Autodesk Fusion 360 part; units mm, degrees
(part 2 of 2)
equation "bolt_line_y = pod_d / 2 - skin_t - bond_t - tube_d / 2" comment "CONFIRMED: J-WALL-02 bolt line on the back panel's tube centre, Y 824 (joints register R-J15, FR-07)"
equation "rivnut_d = 9.53 mm" comment "SOURCE: Sherex CAH3-610-4.2 hole 9.53 +0.10 (HW-SEL A5; register H-03)"
equation "spigot_d = 8.5 mm" comment "ASSUMPTION: register FR-05: hole for the 8 mm locating spigot H-05"
equation "spigot_slot = 14 mm" comment "ASSUMPTION: register FR-05: slot length for the second spigot"
equation "spigot_edge = spigot_inset" comment "CALCULATION: the skeleton's spigot_inset: spigots 100 from each end of the edge (PM ruling 2026-10-31, R-J13)"
equation "bolt_edge = bolt_edge_inset" comment "CALCULATION: the skeleton's bolt_edge_inset: end bolts 220 in from the panel's ends, evenly spaced, every bolt 30 or more from any stile (PM ruling 2026-10-31, R-J14)"
equation "n_side_jnt = 3" comment "SOURCE: register J-WALL-02, J-FRONT-01: 3 bolts up each side panel"
equation "side_jnt_pitch = ( pnl_h - 2 * bolt_edge ) / ( n_side_jnt - 1 )" comment "CALCULATION: equal pitch of the 3 bolts up the corner and decor joints"
equation "pocket_w = 60 mm" comment "ASSUMPTION: register FR-10: fill left out 60 x 60 next to each bolt for the key"
equation "corner_z0 = panel_z0 + back_ph + seam_gap" comment "CALCULATION: bottom of the back panel row this side panel meets at the corner (B1/B2 or B3/B4, skeleton P04)"
equation "corner_bolt_pitch = ( back_ph - 2 * bolt_edge ) / ( n_side_jnt - 1 )" comment "CALCULATION: J-WALL-02 bolts run along the back panel's edge: 220, 559.31, 898.61 on its 1118.61 (joints register 2.9)"
equation "n_len_bolt = n_base_bolt" comment "CALCULATION: the skeleton's n_base_bolt (4): the same count on J-WALL-01 and the J-CEIL-01 side edges (register 2.9)"
equation "ceil_bolt_pitch = ( wall_depth - 2 * bolt_edge ) / ( n_len_bolt - 1 )" comment "CALCULATION: J-CEIL-01 side edge: 4 bolts along the ceiling's 1495 from Y -645 (its front edge), 220 rule, pitch 351.67 on P04; CEILING drills the same (PM ruling 2026-10-31 16:55; joints register 2.9)"
equation "len_bolt_pitch = ( pnl_len - 2 * bolt_edge ) / ( n_len_bolt - 1 )" comment "CALCULATION: even pitch of the bolts along the panel"
equation "felt_t = 9 mm" comment "SOURCE: plan VT03-PET 9 mm PET felt; HW-SEL A3; D-31 (the factory's felt)"
equation "tray_t = 0.5 mm" comment "CONFIRMED: D-37: galvanised steel tray 0.5 mm"
equation "tray_h = cass_t" comment "CONFIRMED: PM ruling 2026-10-31 (WALL group, option 1): the wall cassettes use the ceiling's tray, returns the full cassette depth (34) turned in as lips that hold the felt, no ribs; settles H09 for the walls"
equation "lip_w = 12 mm" comment "CONFIRMED: PM ruling 2026-10-31 (WALL group, option 1): 12 mm lips hold the felt edge"
equation "bend_r = tray_t" comment "ASSUMPTION: inside bend radius 1 x t for 0.5 mm DX51D (the sheet metal rule's bend radius is its Thickness); the factory's tooling sets it (guideline 9)"
equation "felt_c = 1 mm" comment "ASSUMPTION: felt edge clearance inside the returns, as the ceiling cassette"
equation "gap_h = tray_h - felt_t - 2 * tray_t" comment "CALCULATION: air gap between the tray base and the felt (24): the acoustic gap (D-17) and the cable path (D-26)"
equation "cass_len = wall_depth - stack_t + cass_t" comment "CALCULATION: = 1448: from the decor back plate to past the back cassette's face, closing the inside corner (D-57)"
equation "cass_h = pod_h - outer_t - lin_gap - ( panel_z0 + side_h + seam_gap )" comment "CALCULATION: lower: the panel height; upper: stops lin_gap under the roof frame so it floats (D-57)"
equation "clip_zone_h = 60 mm" comment "ASSUMPTION: height of each reserved clip zone (H03: no clip named)"
equation "clip_zone_dz = 100 mm" comment "ASSUMPTION: clip zone centre from the cassette's top and bottom edges (H03)"
equation "stopw_od = 20 mm" comment "SOURCE: joints register H-08: stop washer Ø10.5 x Ø20 x 1.5 (PROPOSED part)"
equation "stopw_id = 10.5 mm" comment "SOURCE: joints register H-08"
equation "stopw_t = 1.5 mm" comment "SOURCE: joints register H-08: rivnut head 0.76 + washer 1.5 = the 2.26 stop (R-J5)"
equation "rivnut_head_d = 12.96 mm" comment "SOURCE: Sherex CAH3-610-4.2 head Ø12.96 (joints register H-03, SHX)"
equation "rivnut_head_t = 0.76 mm" comment "SOURCE: Sherex CAH3-610-4.2 head 0.76 ±0.08 (H-03, SHX)"
equation "rivnut_body_d = 9.5 mm" comment "SOURCE: Sherex CAH3-610-4.2 body Ø9.50 max (H-03, SHX)"
equation "rivnut_len = 10.16 mm" comment "SOURCE: Sherex CAH3-610-4.2 installed length 10.16 max under the head (H-03, SHX); the bulge inside the tube is not modelled"
equation "m6_d = 6 mm" comment "CALCULATION: M6 threads shown at their 6 mm major diameter (no modelled thread)"
equation "spigot_pin_d = 8 mm" comment "SOURCE: joints register H-05: Ø8 stainless pin (PROPOSED, assumption sizes)"
equation "spigot_proud = 8 mm" comment "SOURCE: joints register H-05: stands 8 proud (read as: of the joint face)"
equation "spigot_thread_l = 10 mm" comment "ASSUMPTION: M6 thread into the spigot rivnut; H-05 gives no length; 10 stays inside the rivnut's 10.16"
equation "d660 = panel_z0 + side_h + seam_gap"
equation "d662 = ( -( pod_w / 2 - outer_t ) ) - ( -( pod_w / 2 - skin_t - bond_t ) )"
equation "d663 = ( pod_d / 2 - skin_t ) - ( pod_d / 2 - wall_depth + seam_gap )"
equation "d664 = abs(-( pod_w / 2 - skin_t - bond_t ))"
equation "d665 = abs(pod_d / 2 - wall_depth + seam_gap)"
equation "d666 = ( ( panel_z0 + side_h + seam_gap ) + tube_w ) - ( panel_z0 + side_h + seam_gap )"
equation "d668 = ( panel_z0 + side_h + seam_gap ) + tube_t"
equation "d670 = ( ( -( pod_w / 2 - outer_t ) ) - tube_t ) - ( ( -( pod_w / 2 - skin_t - bond_t ) ) + tube_t )"
equation "d671 = ( pod_d / 2 - skin_t ) - ( pod_d / 2 - wall_depth + seam_gap )"
equation "d672 = abs(( -( pod_w / 2 - skin_t - bond_t ) ) + tube_t)"
equation "d673 = abs(pod_d / 2 - wall_depth + seam_gap)"
equation "d674 = ( ( ( panel_z0 + side_h + seam_gap ) + tube_w ) - tube_t ) - ( ( panel_z0 + side_h + seam_gap ) + tube_t )"
equation "d676 = ( pod_h ) - top_h"
equation "d678 = ( -( pod_w / 2 - outer_t ) ) - ( -( pod_w / 2 - skin_t - bond_t ) )"
equation "d679 = ( pod_d / 2 - skin_t ) - ( pod_d / 2 - wall_depth + seam_gap )"
equation "d680 = abs(-( pod_w / 2 - skin_t - bond_t ))"
equation "d681 = abs(pod_d / 2 - wall_depth + seam_gap)"
equation "d682 = ( pod_h ) - ( ( pod_h ) - top_h )"
equation "d684 = ( ( pod_h ) - top_h ) + tube_t"
equation "d686 = ( ( -( pod_w / 2 - outer_t ) ) - tube_t ) - ( ( -( pod_w / 2 - skin_t - bond_t ) ) + tube_t )"
equation "d687 = ( pod_d / 2 - skin_t ) - ( pod_d / 2 - wall_depth + seam_gap )"
equation "d688 = abs(( -( pod_w / 2 - skin_t - bond_t ) ) + tube_t)"
equation "d689 = abs(pod_d / 2 - wall_depth + seam_gap)"
equation "d690 = ( ( pod_h ) - tube_t ) - ( ( ( pod_h ) - top_h ) + tube_t )"
equation "d692 = ( panel_z0 + side_h + seam_gap ) + tube_w"
equation "d694 = ( -( pod_w / 2 - outer_t ) ) - ( -( pod_w / 2 - skin_t - bond_t ) )"
equation "d695 = ( ( pod_d / 2 - wall_depth + seam_gap ) + tube_w ) - ( pod_d / 2 - wall_depth + seam_gap )"
equation "d696 = abs(-( pod_w / 2 - skin_t - bond_t ))"
equation "d697 = abs(pod_d / 2 - wall_depth + seam_gap)"
equation "d698 = ( ( pod_h ) - top_h ) - ( ( panel_z0 + side_h + seam_gap ) + tube_w )"
equation "d700 = ( panel_z0 + side_h + seam_gap ) + tube_w"
equation "d702 = ( ( -( pod_w / 2 - outer_t ) ) - tube_t ) - ( ( -( pod_w / 2 - skin_t - bond_t ) ) + tube_t )"
equation "d703 = ( ( ( pod_d / 2 - wall_depth + seam_gap ) + tube_w ) - tube_t ) - ( ( pod_d / 2 - wall_depth + seam_gap ) + tube_t )"
equation "d704 = abs(( -( pod_w / 2 - skin_t - bond_t ) ) + tube_t)"
equation "d705 = abs(( pod_d / 2 - wall_depth + seam_gap ) + tube_t)"
equation "d706 = ( ( pod_h ) - top_h ) - ( ( panel_z0 + side_h + seam_gap ) + tube_w )"
equation "d708 = ( panel_z0 + side_h + seam_gap ) + tube_w"
equation "d710 = ( -( pod_w / 2 - outer_t ) ) - ( -( pod_w / 2 - skin_t - bond_t ) )"
equation "d711 = ( pod_d / 2 - skin_t ) - ( ( pod_d / 2 - skin_t ) - corner_w )"
equation "d712 = abs(-( pod_w / 2 - skin_t - bond_t ))"
equation "d713 = abs(( pod_d / 2 - skin_t ) - corner_w)"
equation "d714 = ( ( pod_h ) - top_h ) - ( ( panel_z0 + side_h + seam_gap ) + tube_w )"
equation "d716 = ( panel_z0 + side_h + seam_gap ) + tube_w"
equation "d718 = ( ( -( pod_w / 2 - outer_t ) ) - tube_t ) - ( ( -( pod_w / 2 - skin_t - bond_t ) ) + tube_t )"
equation "d719 = ( ( pod_d / 2 - skin_t ) - tube_t ) - ( ( ( pod_d / 2 - skin_t ) - corner_w ) + tube_t )"
equation "d720 = abs(( -( pod_w / 2 - skin_t - bond_t ) ) + tube_t)"
equation "d721 = abs(( ( pod_d / 2 - skin_t ) - corner_w ) + tube_t)"
equation "d722 = ( ( pod_h ) - top_h ) - ( ( panel_z0 + side_h + seam_gap ) + tube_w )"
equation "d724 = ( panel_z0 + side_h + seam_gap ) + tube_w"
equation "d726 = ( -( pod_w / 2 - outer_t ) ) - ( -( pod_w / 2 - skin_t - bond_t ) )"
equation "d727 = ( ( pod_d / 2 - wall_depth + seam_gap ) + stile_pitch + tube_w ) - ( ( pod_d / 2 - wall_depth + seam_gap ) + stile_pitch )"
equation "d728 = abs(-( pod_w / 2 - skin_t - bond_t ))"
equation "d729 = abs(( pod_d / 2 - wall_depth + seam_gap ) + stile_pitch)"
equation "d730 = ( ( pod_h ) - top_h ) - ( ( panel_z0 + side_h + seam_gap ) + tube_w )"
equation "d732 = ( panel_z0 + side_h + seam_gap ) + tube_w"
equation "d734 = ( ( -( pod_w / 2 - outer_t ) ) - stud_t ) - ( ( -( pod_w / 2 - skin_t - bond_t ) ) + stud_t )"
equation "d735 = ( ( ( pod_d / 2 - wall_depth + seam_gap ) + stile_pitch + tube_w ) - stud_t ) - ( ( ( pod_d / 2 - wall_depth + seam_gap ) + stile_pitch ) + stud_t )"
equation "d736 = abs(( -( pod_w / 2 - skin_t - bond_t ) ) + stud_t)"
equation "d737 = abs(( ( pod_d / 2 - wall_depth + seam_gap ) + stile_pitch ) + stud_t)"
equation "d738 = ( ( pod_h ) - top_h ) - ( ( panel_z0 + side_h + seam_gap ) + tube_w )"
equation "d740 = stile_n_mid"
equation "d742 = stile_pitch"
equation "d744 = ( panel_z0 + side_h + seam_gap ) + skin_setback"
equation "d746 = ( -( pod_w / 2 - skin_t ) ) - ( -( pod_w / 2 ) )"
equation "d747 = ( pod_d / 2 ) - ( pod_d / 2 - wall_depth + seam_gap )"
equation "d748 = abs(-( pod_w / 2 ))"
equation "d749 = abs(pod_d / 2 - wall_depth + seam_gap)"
equation "d750 = ( pod_h ) - ( ( panel_z0 + side_h + seam_gap ) + skin_setback )"
equation "d752 = ( panel_z0 + side_h + seam_gap ) + skin_setback"
equation "d754 = ( -( pod_w / 2 - skin_t - skin_ret ) ) - ( -( pod_w / 2 - skin_t ) )"
equation "d755 = ( pod_d / 2 ) - ( pod_d / 2 - skin_t )"
equation "d756 = abs(-( pod_w / 2 - skin_t ))"
equation "d757 = abs(pod_d / 2 - skin_t)"
equation "d758 = ( pod_h ) - ( ( panel_z0 + side_h + seam_gap ) + skin_setback )"
equation "d760 = ( panel_z0 + side_h + seam_gap ) + tube_w"
equation "d762 = ( -( pod_w / 2 - outer_t ) ) - ( -( pod_w / 2 - skin_t - bond_t ) )"
equation "d763 = ( ( pod_d / 2 - wall_depth + seam_gap ) + stile_pitch ) - ( ( pod_d / 2 - wall_depth + seam_gap ) + tube_w )"
equation "d764 = abs(-( pod_w / 2 - skin_t - bond_t ))"
equation "d765 = abs(( pod_d / 2 - wall_depth + seam_gap ) + tube_w)"
equation "d766 = ( ( pod_h ) - top_h ) - ( ( panel_z0 + side_h + seam_gap ) + tube_w )"
equation "d768 = stile_n_mid"
equation "d770 = stile_pitch"
equation "d772 = ( panel_z0 + side_h + seam_gap ) + tube_w"
equation "d774 = ( -( pod_w / 2 - outer_t ) ) - ( -( pod_w / 2 - skin_t - bond_t ) )"
equation "d775 = ( ( pod_d / 2 - skin_t ) - corner_w ) - ( ( pod_d / 2 - wall_depth + seam_gap ) + stile_n_mid * stile_pitch + tube_w )"
equation "d776 = abs(-( pod_w / 2 - skin_t - bond_t ))"
equation "d777 = abs(( pod_d / 2 - wall_depth + seam_gap ) + stile_n_mid * stile_pitch + tube_w)"
equation "d778 = ( ( pod_h ) - top_h ) - ( ( panel_z0 + side_h + seam_gap ) + tube_w )"
equation "d780 = ( panel_z0 + side_h + seam_gap ) + tube_w"
equation "d782 = ( -( pod_w / 2 - outer_t ) ) - ( -( pod_w / 2 - skin_t - bond_t ) )"
equation "d783 = ( ( ( pod_d / 2 - wall_depth + seam_gap ) + bolt_edge + 0 * len_bolt_pitch ) + pocket_w / 2 ) - ( ( ( pod_d / 2 - wall_depth + seam_gap ) + bolt_edge + 0 * len_bolt_pitch ) - pocket_w / 2 )"
equation "d784 = abs(-( pod_w / 2 - skin_t - bond_t ))"
equation "d785 = abs(( ( pod_d / 2 - wall_depth + seam_gap ) + bolt_edge + 0 * len_bolt_pitch ) - pocket_w / 2)"
equation "d786 = ( ( ( panel_z0 + side_h + seam_gap ) + tube_w ) + pocket_w ) - ( ( panel_z0 + side_h + seam_gap ) + tube_w )"
equation "d788 = ( panel_z0 + side_h + seam_gap ) + tube_w"
equation "d790 = ( -( pod_w / 2 - outer_t ) ) - ( -( pod_w / 2 - skin_t - bond_t ) )"
equation "d791 = ( ( ( pod_d / 2 - wall_depth + seam_gap ) + bolt_edge + 1 * len_bolt_pitch ) + pocket_w / 2 ) - ( ( ( pod_d / 2 - wall_depth + seam_gap ) + bolt_edge + 1 * len_bolt_pitch ) - pocket_w / 2 )"
equation "d792 = abs(-( pod_w / 2 - skin_t - bond_t ))"
equation "d793 = abs(( ( pod_d / 2 - wall_depth + seam_gap ) + bolt_edge + 1 * len_bolt_pitch ) - pocket_w / 2)"
equation "d794 = ( ( ( panel_z0 + side_h + seam_gap ) + tube_w ) + pocket_w ) - ( ( panel_z0 + side_h + seam_gap ) + tube_w )"
equation "d796 = ( panel_z0 + side_h + seam_gap ) + tube_w"
equation "d798 = ( -( pod_w / 2 - outer_t ) ) - ( -( pod_w / 2 - skin_t - bond_t ) )"
equation "d799 = ( ( ( pod_d / 2 - wall_depth + seam_gap ) + bolt_edge + 2 * len_bolt_pitch ) + pocket_w / 2 ) - ( ( ( pod_d / 2 - wall_depth + seam_gap ) + bolt_edge + 2 * len_bolt_pitch ) - pocket_w / 2 )"
equation "d800 = abs(-( pod_w / 2 - skin_t - bond_t ))"
equation "d801 = abs(( ( pod_d / 2 - wall_depth + seam_gap ) + bolt_edge + 2 * len_bolt_pitch ) - pocket_w / 2)"
equation "d802 = ( ( ( panel_z0 + side_h + seam_gap ) + tube_w ) + pocket_w ) - ( ( panel_z0 + side_h + seam_gap ) + tube_w )"
equation "d804 = ( panel_z0 + side_h + seam_gap ) + tube_w"
equation "d806 = ( -( pod_w / 2 - outer_t ) ) - ( -( pod_w / 2 - skin_t - bond_t ) )"
equation "d807 = ( ( ( pod_d / 2 - wall_depth + seam_gap ) + bolt_edge + 3 * len_bolt_pitch ) + pocket_w / 2 ) - ( ( ( pod_d / 2 - wall_depth + seam_gap ) + bolt_edge + 3 * len_bolt_pitch ) - pocket_w / 2 )"
equation "d808 = abs(-( pod_w / 2 - skin_t - bond_t ))"
equation "d809 = abs(( ( pod_d / 2 - wall_depth + seam_gap ) + bolt_edge + 3 * len_bolt_pitch ) - pocket_w / 2)"
equation "d810 = ( ( ( panel_z0 + side_h + seam_gap ) + tube_w ) + pocket_w ) - ( ( panel_z0 + side_h + seam_gap ) + tube_w )"
equation "d812 = ( ( ( panel_z0 + side_h + seam_gap ) + bolt_edge ) + 0 * side_jnt_pitch ) - pocket_w / 2"
equation "d814 = ( -( pod_w / 2 - outer_t ) ) - ( -( pod_w / 2 - skin_t - bond_t ) )"
equation "d815 = ( ( pod_d / 2 - wall_depth + seam_gap ) + tube_w + pocket_w ) - ( ( pod_d / 2 - wall_depth + seam_gap ) + tube_w )"
equation "d816 = abs(-( pod_w / 2 - skin_t - bond_t ))"
equation "d817 = abs(( pod_d / 2 - wall_depth + seam_gap ) + tube_w)"
equation "d818 = ( ( ( ( panel_z0 + side_h + seam_gap ) + bolt_edge ) + 0 * side_jnt_pitch ) + pocket_w / 2 ) - ( ( ( ( panel_z0 + side_h + seam_gap ) + bolt_edge ) + 0 * side_jnt_pitch ) - pocket_w / 2 )"
equation "d820 = ( ( ( panel_z0 + side_h + seam_gap ) + bolt_edge ) + 1 * side_jnt_pitch ) - pocket_w / 2"
equation "d822 = ( -( pod_w / 2 - outer_t ) ) - ( -( pod_w / 2 - skin_t - bond_t ) )"
equation "d823 = ( ( pod_d / 2 - wall_depth + seam_gap ) + tube_w + pocket_w ) - ( ( pod_d / 2 - wall_depth + seam_gap ) + tube_w )"
equation "d824 = abs(-( pod_w / 2 - skin_t - bond_t ))"
equation "d825 = abs(( pod_d / 2 - wall_depth + seam_gap ) + tube_w)"
equation "d826 = ( ( ( ( panel_z0 + side_h + seam_gap ) + bolt_edge ) + 1 * side_jnt_pitch ) + pocket_w / 2 ) - ( ( ( ( panel_z0 + side_h + seam_gap ) + bolt_edge ) + 1 * side_jnt_pitch ) - pocket_w / 2 )"
equation "d828 = ( ( ( panel_z0 + side_h + seam_gap ) + bolt_edge ) + 2 * side_jnt_pitch ) - pocket_w / 2"
equation "d830 = ( -( pod_w / 2 - outer_t ) ) - ( -( pod_w / 2 - skin_t - bond_t ) )"
equation "d831 = ( ( pod_d / 2 - wall_depth + seam_gap ) + tube_w + pocket_w ) - ( ( pod_d / 2 - wall_depth + seam_gap ) + tube_w )"
equation "d832 = abs(-( pod_w / 2 - skin_t - bond_t ))"
equation "d833 = abs(( pod_d / 2 - wall_depth + seam_gap ) + tube_w)"
equation "d834 = ( ( ( ( panel_z0 + side_h + seam_gap ) + bolt_edge ) + 2 * side_jnt_pitch ) + pocket_w / 2 ) - ( ( ( ( panel_z0 + side_h + seam_gap ) + bolt_edge ) + 2 * side_jnt_pitch ) - pocket_w / 2 )"
equation "d836 = panel_z0 + side_h + seam_gap"
equation "d838 = abs(-( pod_w / 2 - skin_t - bond_t - tube_d / 2 ))"
equation "d839 = abs(( pod_d / 2 - wall_depth + seam_gap ) + bolt_edge)"
equation "d840 = tube_t"
equation "d841 = bolt_d"
equation "d843 = ( panel_z0 + side_h + seam_gap ) + tube_w"
equation "d845 = abs(-( pod_w / 2 - skin_t - bond_t - tube_d / 2 ))"
equation "d846 = abs(( pod_d / 2 - wall_depth + seam_gap ) + bolt_edge)"
equation "d847 = tube_t"
equation "d848 = access_d"
equation "d850 = n_len_bolt"
equation "d852 = len_bolt_pitch"
equation "d854 = panel_z0 + side_h + seam_gap"
equation "d856 = abs(-( pod_w / 2 - skin_t - bond_t - tube_d / 2 ))"
equation "d857 = abs(( pod_d / 2 - wall_depth + seam_gap ) + spigot_edge)"
equation "d858 = tube_t"
equation "d859 = spigot_d"
equation "d861 = panel_z0 + side_h + seam_gap"
equation "d863 = ( ( -( pod_w / 2 - skin_t - bond_t - tube_d / 2 ) ) + ( spigot_slot - spigot_d ) / 2 ) - ( ( -( pod_w / 2 - skin_t - bond_t - tube_d / 2 ) ) - ( spigot_slot - spigot_d ) / 2 )"
equation "d864 = ( ( ( pod_d / 2 ) - spigot_edge ) + spigot_d / 2 ) - ( ( ( pod_d / 2 ) - spigot_edge ) - spigot_d / 2 )"
equation "d865 = abs(( -( pod_w / 2 - skin_t - bond_t - tube_d / 2 ) ) - ( spigot_slot - spigot_d ) / 2)"
equation "d866 = abs(( ( pod_d / 2 ) - spigot_edge ) - spigot_d / 2)"
equation "d867 = ( ( panel_z0 + side_h + seam_gap ) + tube_t ) - ( panel_z0 + side_h + seam_gap )"
equation "d869 = panel_z0 + side_h + seam_gap"
equation "d871 = abs(( -( pod_w / 2 - skin_t - bond_t - tube_d / 2 ) ) - ( spigot_slot - spigot_d ) / 2)"
equation "d872 = abs(( pod_d / 2 ) - spigot_edge)"
equation "d873 = tube_t"
equation "d874 = spigot_d"
equation "d876 = panel_z0 + side_h + seam_gap"
equation "d878 = abs(( -( pod_w / 2 - skin_t - bond_t - tube_d / 2 ) ) + ( spigot_slot - spigot_d ) / 2)"
equation "d879 = abs(( pod_d / 2 ) - spigot_edge)"
equation "d880 = tube_t"
equation "d881 = spigot_d"
equation "d883 = -( pod_w / 2 - outer_t )"
equation "d885 = abs(( pod_d / 2 - wall_depth ) + bolt_edge)"
equation "d886 = abs(pod_h - ceil_bolt_dz)"
equation "d887 = tube_t"
equation "d888 = rivnut_d"
equation "d890 = n_len_bolt"
equation "d892 = ceil_bolt_pitch"
equation "d894 = pod_d / 2 - wall_depth + seam_gap"
equation "d896 = abs(-( pod_w / 2 - skin_t - bond_t - tube_d / 2 ))"
equation "d897 = abs(( panel_z0 + side_h + seam_gap ) + bolt_edge)"
equation "d898 = tube_t"
equation "d899 = bolt_d"
equation "d901 = ( pod_d / 2 - wall_depth + seam_gap ) + tube_w"
equation "d903 = abs(-( pod_w / 2 - skin_t - bond_t - tube_d / 2 ))"
equation "d904 = abs(( panel_z0 + side_h + seam_gap ) + bolt_edge)"
equation "d905 = tube_t"
equation "d906 = access_d"
equation "d908 = n_side_jnt"
equation "d910 = side_jnt_pitch"
equation "d912 = -( pod_w / 2 - outer_t )"
equation "d914 = abs(bolt_line_y)"
equation "d915 = abs(corner_z0 + bolt_edge)"
equation "d916 = tube_t"
equation "d917 = rivnut_d"
equation "d919 = n_side_jnt"
equation "d921 = corner_bolt_pitch"
equation "d923 = -( pod_w / 2 - outer_t )"
equation "d925 = abs(( pod_d / 2 - wall_depth ) + bolt_edge)"
equation "d926 = abs(pod_h - ceil_bolt_dz)"
equation "d927 = stopw_od"
equation "d928 = stopw_id"
equation "d929 = stopw_t"
equation "d931 = ( -( pod_w / 2 - outer_t ) ) + stopw_t"
equation "d933 = abs(( pod_d / 2 - wall_depth ) + bolt_edge)"
equation "d934 = abs(pod_h - ceil_bolt_dz)"
equation "d935 = rivnut_head_d"
equation "d936 = m6_d"
equation "d937 = rivnut_head_t"
equation "d939 = ( -( pod_w / 2 - outer_t ) ) + stopw_t"
equation "d941 = abs(( pod_d / 2 - wall_depth ) + bolt_edge)"
equation "d942 = abs(pod_h - ceil_bolt_dz)"
equation "d943 = rivnut_body_d"
equation "d944 = m6_d"
equation "d947 = -( rivnut_len )"
equation "d949 = n_len_bolt"
equation "d951 = ceil_bolt_pitch"
equation "d953 = n_len_bolt"
equation "d955 = ceil_bolt_pitch"
equation "d957 = -( pod_w / 2 - outer_t )"
equation "d959 = abs(bolt_line_y)"
equation "d960 = abs(corner_z0 + bolt_edge)"
equation "d961 = stopw_od"
equation "d962 = stopw_id"
equation "d963 = stopw_t"
equation "d965 = ( -( pod_w / 2 - outer_t ) ) + stopw_t"
equation "d967 = abs(bolt_line_y)"
equation "d968 = abs(corner_z0 + bolt_edge)"
equation "d969 = rivnut_head_d"
equation "d970 = m6_d"
equation "d971 = rivnut_head_t"
equation "d973 = ( -( pod_w / 2 - outer_t ) ) + stopw_t"
equation "d975 = abs(bolt_line_y)"
equation "d976 = abs(corner_z0 + bolt_edge)"
equation "d977 = rivnut_body_d"
equation "d978 = m6_d"
equation "d981 = -( rivnut_len )"
equation "d983 = n_side_jnt"
equation "d985 = corner_bolt_pitch"
equation "d987 = n_side_jnt"
equation "d989 = corner_bolt_pitch"
named bodies: "RAIL - BOTTOM", "RAIL - TOP", "STILE - FRONT", "STILE - BACK", "STILE - MID 1", "STILE - MID 2", "STILE - MID 3", "SKIN - ACP 3 WITH BACK RETURN", "FILL - BAY 1", "FILL - BAY 2", "FILL - BAY 3", "FILL - BAY 4", "STOP WASHER - TOP MEMBER CEILING 1", "RIVNUT - TOP MEMBER CEILING 1", "STOP WASHER - TOP MEMBER CEILING 2", "STOP WASHER - TOP MEMBER CEILING 3", "STOP WASHER - TOP MEMBER CEILING 4", "RIVNUT - TOP MEMBER CEILING 2", "RIVNUT - TOP MEMBER CEILING 3", "RIVNUT - TOP MEMBER CEILING 4", "STOP WASHER - BACK STILE CORNER 1", "RIVNUT - BACK STILE CORNER 1", "STOP WASHER - BACK STILE CORNER 2", "STOP WASHER - BACK STILE CORNER 3", "RIVNUT - BACK STILE CORNER 2", "RIVNUT - BACK STILE CORNER 3"
